Autodesk Inventor part; units mm, degrees
(part 2 of 2)
sketch "스케치8" plane through (-30.2, 45.5, -10) normal (0, 1, 0) x (1, 0, 0)
  circle A0 centre (0, 0) radius 6.5 projected
  circle A1 centre (0, 0) radius 1.25
  circle A2 centre (0, 0) radius 3 projected
  line L0 (0, -3) -> (0.3133, -2.4803)
  line L1 (0, -3) -> (-0.3133, -2.4803)
  line L2 (0.3133, -2.4803) -> (0, 0) construction
  line L3 (0, 0) -> (-0.3133, -2.4803) construction
  line L4 (0, -3) -> (0, 0) construction
  line L5 (0.7461, -2.9057) -> (0.3133, -2.4803)
  line L6 (0.7461, -2.9057) -> (0.9203, -2.3244)
  line L7 (1.4453, -2.6289) -> (0.9203, -2.3244)
  line L8 (1.4453, -2.6289) -> (1.4695, -2.0225)
  line L9 (2.0536, -2.1869) -> (1.4695, -2.0225)
  line L10 (2.0536, -2.1869) -> (1.9263, -1.5936)
  line L11 (2.533, -1.6075) -> (1.9263, -1.5936)
  line L12 (2.533, -1.6075) -> (2.2621, -1.0644)
  line L13 (2.8532, -0.9271) -> (2.2621, -1.0644)
  line L14 (2.8532, -0.9271) -> (2.4557, -0.4685)
  line L15 (2.9941, -0.1884) -> (2.4557, -0.4685)
  line L16 (2.9941, -0.1884) -> (2.4951, 0.157)
  line L17 (2.9469, 0.5621) -> (2.4951, 0.157)
  line L18 (2.9469, 0.5621) -> (2.3776, 0.7725)
  line L19 (2.7145, 1.2773) -> (2.3776, 0.7725)
  line L20 (2.7145, 1.2773) -> (2.1108, 1.3396)
  line L21 (2.3115, 1.9123) -> (2.1108, 1.3396)
  line L22 (2.3115, 1.9123) -> (1.7114, 1.8224)
  line L23 (1.7634, 2.4271) -> (1.7114, 1.8224)
  line L24 (1.7634, 2.4271) -> (1.2044, 2.1908)
  line L25 (1.1044, 2.7893) -> (1.2044, 2.1908)
  line L26 (1.1044, 2.7893) -> (0.6217, 2.4215)
  line L27 (0.376, 2.9763) -> (0.6217, 2.4215)
  line L28 (0.376, 2.9763) -> (0, 2.5)
  line L29 (-0.376, 2.9763) -> (0, 2.5)
  line L30 (-0.376, 2.9763) -> (-0.6217, 2.4215)
  line L31 (-1.1044, 2.7893) -> (-0.6217, 2.4215)
  line L32 (-1.1044, 2.7893) -> (-1.2044, 2.1908)
  line L33 (-1.7634, 2.4271) -> (-1.2044, 2.1908)
  line L34 (-1.7634, 2.4271) -> (-1.7114, 1.8224)
  line L35 (-2.3115, 1.9123) -> (-1.7114, 1.8224)
  line L36 (-2.3115, 1.9123) -> (-2.1108, 1.3396)
  line L37 (-2.7145, 1.2773) -> (-2.1108, 1.3396)
  line L38 (-2.7145, 1.2773) -> (-2.3776, 0.7725)
  line L39 (-2.9469, 0.5621) -> (-2.3776, 0.7725)
  line L40 (-2.9469, 0.5621) -> (-2.4951, 0.157)
  line L41 (-2.9941, -0.1884) -> (-2.4951, 0.157)
  line L42 (-2.9941, -0.1884) -> (-2.4557, -0.4685)
  line L43 (-2.8532, -0.9271) -> (-2.4557, -0.4685)
  line L44 (-2.8532, -0.9271) -> (-2.2621, -1.0644)
  line L45 (-2.533, -1.6075) -> (-2.2621, -1.0644)
  line L46 (-2.533, -1.6075) -> (-1.9263, -1.5936)
  line L47 (-2.0536, -2.1869) -> (-1.9263, -1.5936)
  line L48 (-2.0536, -2.1869) -> (-1.4695, -2.0225)
  line L49 (-1.4453, -2.6289) -> (-1.4695, -2.0225)
  line L50 (-1.4453, -2.6289) -> (-0.9203, -2.3244)
  line L51 (-0.7461, -2.9057) -> (-0.9203, -2.3244)
  line L52 (-0.7461, -2.9057) -> (-0.3133, -2.4803)
  circle A3 centre (0, 0) radius 2.5 projected
  point P0 (30.2, -10)
  point P1 (-0.7461, -2.9057)
  point P2 (-0.7461, -2.9057)
  point P3 (-1.4453, -2.6289)
  point P4 (-1.4453, -2.6289)
  point P5 (-2.0536, -2.1869)
  point P6 (-2.0536, -2.1869)
  point P7 (-2.533, -1.6075)
  point P8 (-2.533, -1.6075)
  point P9 (-2.8532, -0.9271)
  point P10 (-2.8532, -0.9271)
  point P11 (-2.4557, -0.4685)
  point P12 (-2.9941, -0.1884)
  point P13 (-2.9941, -0.1884)
  point P14 (-2.4951, 0.157)
  point P15 (-2.9469, 0.5621)
  point P16 (-2.9469, 0.5621)
  point P17 (-2.3776, 0.7725)
  point P18 (-2.7145, 1.2773)
  point P19 (-2.7145, 1.2773)
  point P20 (-2.3115, 1.9123)
  point P21 (-2.3115, 1.9123)
  point P22 (-1.7114, 1.8224)
  point P23 (-1.7634, 2.4271)
  point P24 (-1.7634, 2.4271)
  point P25 (-1.2044, 2.1908)
  point P26 (-1.1044, 2.7893)
  point P27 (-1.1044, 2.7893)
  point P28 (-0.6217, 2.4215)
  point P29 (-0.376, 2.9763)
  point P30 (-0.376, 2.9763)
  point P31 (0, 2.5)
  point P32 (0.376, 2.9763)
  point P33 (0.376, 2.9763)
  point P34 (0.6217, 2.4215)
  point P35 (1.1044, 2.7893)
  point P36 (1.1044, 2.7893)
  point P37 (1.7634, 2.4271)
  point P38 (1.7634, 2.4271)
  point P39 (1.7114, 1.8224)
  point P40 (2.3115, 1.9123)
  point P41 (2.3115, 1.9123)
  point P42 (2.7145, 1.2773)
  point P43 (2.7145, 1.2773)
  point P44 (2.9469, 0.5621)
  point P45 (2.9469, 0.5621)
  point P46 (2.4951, 0.157)
  point P47 (2.9941, -0.1884)
  point P48 (2.9941, -0.1884)
  point P49 (2.4557, -0.4685)
  point P50 (2.8532, -0.9271)
  point P51 (2.8532, -0.9271)
  point P52 (2.533, -1.6075)
  point P53 (2.533, -1.6075)
  point P54 (2.0536, -2.1869)
  point P55 (2.0536, -2.1869)
  point P56 (1.4453, -2.6289)
  point P57 (1.4453, -2.6289)
  point P58 (0.9203, -2.3244)
  point P59 (0.7461, -2.9057)
  point P60 (0.7461, -2.9057)
  dimension "d58" = 2.5
  dimension "d62" = 14.4
  dimension "d63" = 7.2
  dimension "d66" = 360
  constraints: 106 end point, 1 centre point, 1 coincident, 1 horizontal alignment, 1 vertical, 130 other
  measures "d58" diameter of A1
  measures "d62" angle of L2 L3
  measures "d63" angle of L4 L3
extrude "돌출8" cut sketch "스케치8" against normal blind 5 contours A1 | A2 L16 L17 | L18 L19 A2 | A2 L14 L15 | L20 L21 A2 | A2 L12 L13 | L22 L23 A2 | A2 L10 L11 | L24 L25 A2 | A2 L8 L9 | L26 L27 A2 | A2 L6 L7 | L28 L29 A2 | A2 L0 L5 | L30 L31 A2 | A2 L52 L1 | L32 L33 A2 | A2 L50 L51 | L34 L35 A2 | A2 L48 L49 | L36 L37 A2 | A2 L46 L47 | L38 L39 A2 | A2 L44 L45 | L40 L41 A2 | A2 L42 L43
thread "스레드1" size "M2.5x0.45" class "6H" standard "ANSI Metric M Profile" full length
chamfer "모따기3" distance 0.5 angle 45 1 edges at (-31.45, 45.5, -10)
equation "\"d14\" = d13"
equation "\"d18\" = d17"
equation "\"d19\" = d17"
equation "\"d20\" = d17"
equation "\"d32\" = d31"
equation "\"d24\" = d21"
equation "\"d63\" = 0.5 * d62"
equation "\"d21\" = 48.6"
